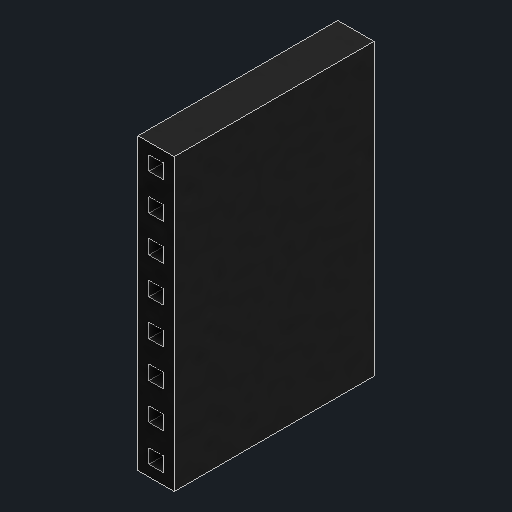
# Autodesk Inventor part: dupont_1x8_housing_tft
Saved by Autodesk Inventor 2027.1 (Build 311270010, 270A)
## iProperties
Created: 2026-10-29
Part Number: dupont_1x8_housing_tft
Material: Generic
Document SubType Name: Modeling
Designer: alexg
Density: 1 g/cm^3
Appearance: Black
Author: alexg
Autodesk Inventor part; units mm, degrees
ref_plane "YZ Plane" through (0, 0, 0) normal (1, 0, 0) x (0, 1, 0)
ref_plane "Work Plane1" through (0, 0, 21.3) normal (0, 0, 1) x (1, 0, 0)
sketch "Body sketch" plane through (0, 0, 21.3) normal (0, 0, 1) x (1, 0, 0)
  line L0 (22.31, 32.34) -> (24.85, 32.34)
  line L1 (24.85, 32.34) -> (24.85, 52.66)
  line L2 (24.85, 52.66) -> (22.31, 52.66)
  line L3 (22.31, 52.66) -> (22.31, 32.34)
  constraints: 8 end point, 2 parallel, 1 horizontal, 1 perpendicular
extrude "Body" add sketch "Body sketch" against normal blind 14
ref_plane "Work Plane2" through (0, 0, 21.3) normal (0, 0, 1) x (1, 0, 0)
sketch "Pin sockets sketch" plane through (0, 0, 21.3) normal (0, 0, 1) x (1, 0, 0)
  line L0 (23.08, 33.11) -> (24.08, 33.11)
  line L1 (24.08, 33.11) -> (24.08, 34.11)
  line L2 (24.08, 34.11) -> (23.08, 34.11)
  line L3 (23.08, 34.11) -> (23.08, 33.11)
  line L4 (23.08, 35.65) -> (24.08, 35.65)
  line L5 (24.08, 35.65) -> (24.08, 36.65)
  line L6 (24.08, 36.65) -> (23.08, 36.65)
  line L7 (23.08, 36.65) -> (23.08, 35.65)
  line L8 (23.08, 38.19) -> (24.08, 38.19)
  line L9 (24.08, 38.19) -> (24.08, 39.19)
  line L10 (24.08, 39.19) -> (23.08, 39.19)
  line L11 (23.08, 39.19) -> (23.08, 38.19)
  line L12 (23.08, 40.73) -> (24.08, 40.73)
  line L13 (24.08, 40.73) -> (24.08, 41.73)
  line L14 (24.08, 41.73) -> (23.08, 41.73)
  line L15 (23.08, 41.73) -> (23.08, 40.73)
  line L16 (23.08, 43.27) -> (24.08, 43.27)
  line L17 (24.08, 43.27) -> (24.08, 44.27)
  line L18 (24.08, 44.27) -> (23.08, 44.27)
  line L19 (23.08, 44.27) -> (23.08, 43.27)
  line L20 (23.08, 45.81) -> (24.08, 45.81)
  line L21 (24.08, 45.81) -> (24.08, 46.81)
  line L22 (24.08, 46.81) -> (23.08, 46.81)
  line L23 (23.08, 46.81) -> (23.08, 45.81)
  line L24 (23.08, 48.35) -> (24.08, 48.35)
  line L25 (24.08, 48.35) -> (24.08, 49.35)
  line L26 (24.08, 49.35) -> (23.08, 49.35)
  line L27 (23.08, 49.35) -> (23.08, 48.35)
  line L28 (23.08, 50.89) -> (24.08, 50.89)
  line L29 (24.08, 50.89) -> (24.08, 51.89)
  line L30 (24.08, 51.89) -> (23.08, 51.89)
  line L31 (23.08, 51.89) -> (23.08, 50.89)
  constraints: 64 end point, 16 parallel, 8 horizontal, 8 perpendicular
extrude "Pin sockets" cut sketch "Pin sockets sketch" against normal blind 7
body "Solid1"
